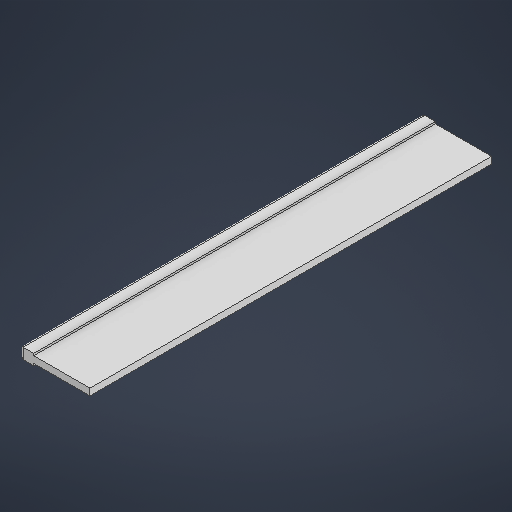
# Autodesk Inventor part: Brush Sweeper
Saved by Autodesk Inventor 2026.2 (Build 302298010, 298A)
## iProperties
Created: 2026-03-26
Part Number: Brush Sweeper
Material: Generic
Document SubType Name: Modeling
Designer: User
Density: 1 g/cm^3
Appearance: Default
Author: User
Autodesk Inventor part; units mm, degrees
ref_plane "YZ Plane" through (0, 0, 0) normal (1, 0, 0) x (0, 1, 0)
ref_plane "XZ Plane" through (0, 0, 0) normal (0, 1, 0) x (-1, 0, 0)
ref_plane "XY Plane" through (0, 0, 0) normal (0, 0, 1) x (1, 0, 0)
sketch "Sketch1" plane through (0, 0, 0) normal (0, 1, 0) x (-1, 0, 0)
  line L0 (10.5, 75) -> (-10.5, 75)
  line L1 (-10.5, 75) -> (-10.5, -75)
  line L2 (-10.5, -75) -> (10.5, -75)
  line L3 (10.5, -75) -> (10.5, 75)
  line L4 (10.5, 75) -> (-10.5, -75) construction
  line L5 (-10.5, 75) -> (10.5, -75) construction
  point P0 (0, 0)
  dimension "d0" = 21
  dimension "d1" = 150
  constraints: 12 end point, 2 midpoint, 2 parallel, 1 horizontal, 1 perpendicular
  measures "d0" distance of L1.end L2.end
  measures "d1" distance of L2.end L0.start
extrude "Extrusion1" add sketch "Sketch1" along normal mid plane 2.5
sketch "Sketch2" plane through (-10.5, -1.25, 75) normal (-1, 0, 0) x (0, 0, 1)
  line L0 (-150, 3.25) -> (0, 3.25)
  line L1 (0, 3.25) -> (0, -0.75)
  line L2 (0, -0.75) -> (-150, -0.75)
  line L3 (-150, -0.75) -> (-150, 3.25)
  line L4 (-150, 3.25) -> (0, -0.75) construction
  line L5 (0, 3.25) -> (-150, -0.75) construction
  point P0 (-75, 1.25)
  dimension "d4" = 150
  dimension "d5" = 4
  constraints: 12 end point, 2 midpoint, 2 parallel, 1 horizontal, 1 perpendicular
  measures "d4" distance of L1.end L2.end
  measures "d5" distance of L0.end L1.end
extrude "Extrusion2" add sketch "Sketch2" along normal blind 5
fillet "Fillet1" radius 1 4 edges at (-15.5, 0, 75) (-15.5, 2, 0) (-15.5, -2, 0) (-15.5, 0, -75)
body "Solid1"
